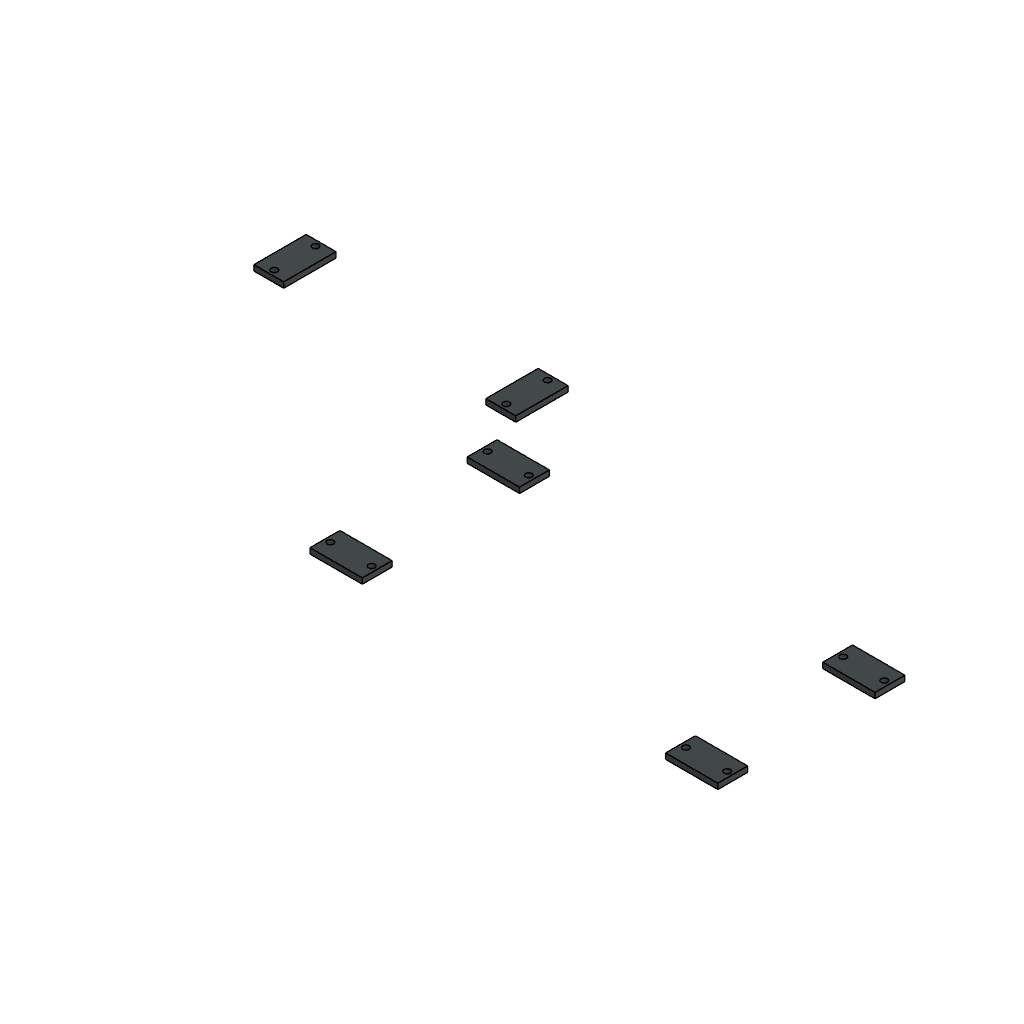
05-printable-rear-joining-bridges (Autodesk Fusion 360 design; units mm, degrees)
part number: 2026-10-09-16-49-26-535
Autodesk Fusion 360 part; units mm, degrees
ref_plane "WorkPlane1" through (0, 0, -45) normal (0, 0, 1) x (1, 0, 0)
sketch "Rear joining bridge - print six footprint" plane through (0, 0, -45) normal (0, 0, 1) x (1, 0, 0)
  line L0 (166, 20) -> (194, 20)
  line L1 (194, 20) -> (194, 36)
  line L2 (194, 36) -> (166, 36)
  line L3 (166, 36) -> (166, 20)
extrude "Rear joining bridge - print six" add sketch "Rear joining bridge - print six footprint" along normal blind 3 makes body 1
ref_plane "WorkPlane2" through (0, 0, -42) normal (0, 0, 1) x (1, 0, 0)
sketch "Bridge M3 bolt holes" plane through (0, 0, -42) normal (0, 0, 1) x (1, 0, 0)
  circle A0 centre (169, 28) radius 1.7
  circle A1 centre (191, 28) radius 1.7
  dimension "d1305" = 3.4
  dimension "d1306" = 3.4
  measures "d1305" diameter of A0
  measures "d1306" diameter of A1
extrude "Bridge M3 bolt holes cut" cut sketch "Bridge M3 bolt holes" against normal blind 3 bodies 1
ref_plane "WorkPlane3" through (0, 0, -45) normal (0, 0, 1) x (1, 0, 0)
sketch "Rear bridge at 180 112 footprint" plane through (0, 0, -45) normal (0, 0, 1) x (1, 0, 0)
  line L0 (166, 104) -> (194, 104)
  line L1 (194, 104) -> (194, 120)
  line L2 (194, 120) -> (166, 120)
  line L3 (166, 120) -> (166, 104)
extrude "Rear bridge at 180 112" add sketch "Rear bridge at 180 112 footprint" along normal blind 3 separate body makes body 2
ref_plane "WorkPlane4" through (0, 0, -42) normal (0, 0, 1) x (1, 0, 0)
sketch "Bridge M3 holes" plane through (0, 0, -42) normal (0, 0, 1) x (1, 0, 0)
  circle A0 centre (169, 112) radius 1.7
  circle A1 centre (191, 112) radius 1.7
  dimension "d1315" = 3.4
  dimension "d1316" = 3.4
  measures "d1315" diameter of A0
  measures "d1316" diameter of A1
extrude "Bridge M3 holes cut" cut sketch "Bridge M3 holes" against normal blind 3 bodies 2
ref_plane "WorkPlane5" through (0, 0, -45) normal (0, 0, 1) x (1, 0, 0)
sketch "Rear bridge at 370 28 footprint" plane through (0, 0, -45) normal (0, 0, 1) x (1, 0, 0)
  line L0 (356, 20) -> (384, 20)
  line L1 (384, 20) -> (384, 36)
  line L2 (384, 36) -> (356, 36)
  line L3 (356, 36) -> (356, 20)
extrude "Rear bridge at 370 28" add sketch "Rear bridge at 370 28 footprint" along normal blind 3 separate body makes body 3
ref_plane "WorkPlane6" through (0, 0, -42) normal (0, 0, 1) x (1, 0, 0)
sketch "Bridge M3 holes (1)" plane through (0, 0, -42) normal (0, 0, 1) x (1, 0, 0)
  circle A0 centre (359, 28) radius 1.7
  circle A1 centre (381, 28) radius 1.7
  dimension "d1325" = 3.4
  dimension "d1326" = 3.4
  measures "d1325" diameter of A0
  measures "d1326" diameter of A1
extrude "Bridge M3 holes cut (1)" cut sketch "Bridge M3 holes (1)" against normal blind 3 bodies 3
ref_plane "WorkPlane7" through (0, 0, -45) normal (0, 0, 1) x (1, 0, 0)
sketch "Rear bridge at 370 112 footprint" plane through (0, 0, -45) normal (0, 0, 1) x (1, 0, 0)
  line L0 (356, 104) -> (384, 104)
  line L1 (384, 104) -> (384, 120)
  line L2 (384, 120) -> (356, 120)
  line L3 (356, 120) -> (356, 104)
extrude "Rear bridge at 370 112" add sketch "Rear bridge at 370 112 footprint" along normal blind 3 separate body makes body 4
ref_plane "WorkPlane8" through (0, 0, -42) normal (0, 0, 1) x (1, 0, 0)
sketch "Bridge M3 holes (2)" plane through (0, 0, -42) normal (0, 0, 1) x (1, 0, 0)
  circle A0 centre (359, 112) radius 1.7
  circle A1 centre (381, 112) radius 1.7
  dimension "d1335" = 3.4
  dimension "d1336" = 3.4
  measures "d1335" diameter of A0
  measures "d1336" diameter of A1
extrude "Bridge M3 holes cut (2)" cut sketch "Bridge M3 holes (2)" against normal blind 3 bodies 4
ref_plane "WorkPlane9" through (0, 0, -45) normal (0, 0, 1) x (1, 0, 0)
sketch "APU rear bridge at 28 footprint" plane through (0, 0, -45) normal (0, 0, 1) x (1, 0, 0)
  line L0 (20, 136) -> (36, 136)
  line L1 (36, 136) -> (36, 164)
  line L2 (36, 164) -> (20, 164)
  line L3 (20, 164) -> (20, 136)
extrude "APU rear bridge at 28" add sketch "APU rear bridge at 28 footprint" along normal blind 3 separate body makes body 5
ref_plane "WorkPlane10" through (0, 0, -42) normal (0, 0, 1) x (1, 0, 0)
sketch "APU bridge M3 holes" plane through (0, 0, -42) normal (0, 0, 1) x (1, 0, 0)
  circle A0 centre (28, 139) radius 1.7
  circle A1 centre (28, 161) radius 1.7
  dimension "d1345" = 3.4
  dimension "d1346" = 3.4
  measures "d1345" diameter of A0
  measures "d1346" diameter of A1
extrude "APU bridge M3 holes cut" cut sketch "APU bridge M3 holes" against normal blind 3 bodies 5
ref_plane "WorkPlane11" through (0, 0, -45) normal (0, 0, 1) x (1, 0, 0)
sketch "APU rear bridge at 152 footprint" plane through (0, 0, -45) normal (0, 0, 1) x (1, 0, 0)
  line L0 (144, 136) -> (160, 136)
  line L1 (160, 136) -> (160, 164)
  line L2 (160, 164) -> (144, 164)
  line L3 (144, 164) -> (144, 136)
extrude "APU rear bridge at 152" add sketch "APU rear bridge at 152 footprint" along normal blind 3 separate body makes body 6
ref_plane "WorkPlane12" through (0, 0, -42) normal (0, 0, 1) x (1, 0, 0)
sketch "APU bridge M3 holes (1)" plane through (0, 0, -42) normal (0, 0, 1) x (1, 0, 0)
  circle A0 centre (152, 139) radius 1.7
  circle A1 centre (152, 161) radius 1.7
  dimension "d1355" = 3.4
  dimension "d1356" = 3.4
  measures "d1355" diameter of A0
  measures "d1356" diameter of A1
extrude "APU bridge M3 holes cut (1)" cut sketch "APU bridge M3 holes (1)" against normal blind 3 bodies 6
equation "d1305 = mountBore"
equation "d1306 = mountBore"
equation "d1315 = mountBore"
equation "d1316 = mountBore"
equation "d1325 = mountBore"
equation "d1326 = mountBore"
equation "d1335 = mountBore"
equation "d1336 = mountBore"
equation "d1345 = mountBore"
equation "d1346 = mountBore"
equation "d1355 = mountBore"
equation "d1356 = mountBore"
equation "mountBore = 3.4 mm" comment "M3 through-bolt clearance"
named bodies: "Rear joining bridge - print six", "Rear bridge at 180 112", "Rear bridge at 370 28", "Rear bridge at 370 112", "APU rear bridge at 28", "APU rear bridge at 152"
